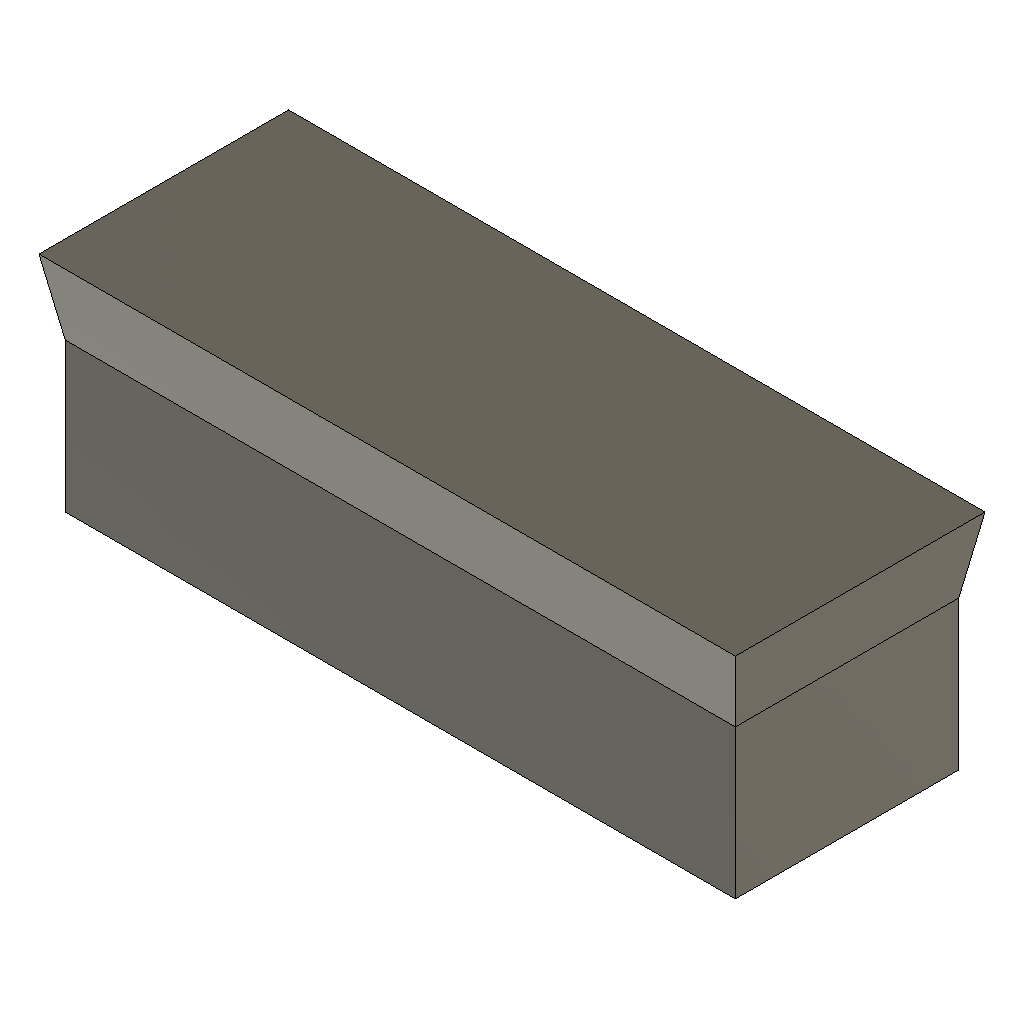
f2sc-test-face-extrude (Autodesk Fusion 360 design; units mm, degrees)
part number: 2026-11-27-15-51-38-027
Autodesk Fusion 360 part; units mm, degrees
sketch "Sketch1" plane through (0, 0, 0) normal (0, 0, 1) x (1, 0, 0)
  line L0 (-25, 25) -> (20, 25)
  line L1 (20, 25) -> (20, 40)
  line L2 (20, 40) -> (-25, 40)
  line L3 (-25, 40) -> (-25, 25)
  constraint horizontal L0
  constraint vertical L1
  constraint horizontal L2
  constraint vertical L3
extrude "Extrude1" add sketch "Sketch1" along normal blind 10
extrude "Extrude2" add 1 faces at (-10, 30, 10) along direction (0, 0, 1) blind 5 draft 10
